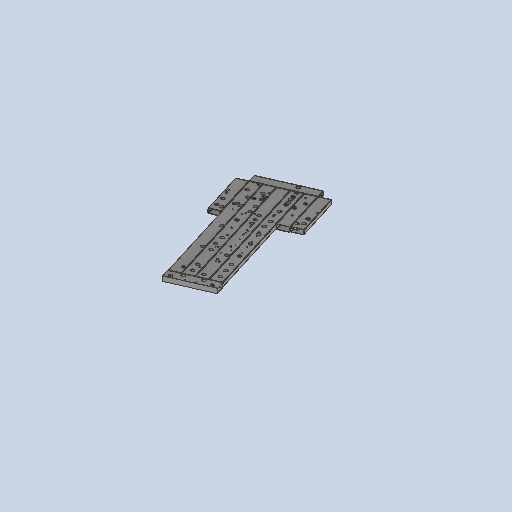
# Autodesk Inventor part: Bauteil1
Saved by Autodesk Inventor 2027.1 (Build 311270010, 270A)
## iProperties
Created: 2026-07-23
Part Number: Bauteil1
Material: Stahl, Kohlenstoff
Document SubType Name: Modeling
Designer: Leander
Density: 7.85 g/cm^3
Appearance: Halbpoliert
Author: Leander
Autodesk Inventor part; units mm, degrees
ref_plane "YZ Plane" through (0, 0, 0) normal (1, 0, 0) x (0, 1, 0)
ref_plane "XZ Plane" through (0, 0, 0) normal (0, 1, 0) x (-1, 0, 0)
sketch "Skizze1" plane through (0, 0, 0) normal (0, 0, 1) x (1, 0, 0)
  line L0 (0, 0) -> (700, 0)
  line L1 (700, 0) -> (700, 1705)
  line L2 (700, 1705) -> (0, 1705)
  line L3 (0, 1705) -> (0, 0)
  line L4 (100, 0) -> (100, 1099)
  line L5 (100, 1099) -> (0, 1099)
  line L6 (0, 1099) -> (0, 1604)
  line L7 (0, 1604) -> (100, 1604)
  line L8 (100, 1604) -> (100, 1705)
  line L9 (100, 1705) -> (600, 1705)
  line L10 (600, 1705) -> (600, 1604)
  line L11 (600, 1604) -> (700, 1604)
  line L12 (700, 1604) -> (700, 1099)
  line L13 (700, 1099) -> (600, 1099)
  line L14 (600, 1099) -> (600, 1089.4)
  line L15 (600, 1089.4) -> (500, 1089.4)
  line L16 (500, 1089.4) -> (500, 0)
  line L17 (100, 0) -> (500, 0)
  circle A0 centre (146.4, 28.6) radius 12.6
  circle A1 centre (146.4, 28.6) radius 16.5
  circle A2 centre (223.4, 69.6) radius 12.6
  circle A3 centre (223.4, 69.6) radius 16.5
  circle A4 centre (373.6, 69.6) radius 12.6
  circle A5 centre (373.6, 69.6) radius 16.5
  circle A6 centre (450.8, 28.6) radius 12.6
  circle A7 centre (450.8, 28.6) radius 16.5
  circle A8 centre (76.1, 1158) radius 12.6
  circle A9 centre (76.1, 1158) radius 16.5
  circle A10 centre (34, 1178) radius 12.6
  circle A11 centre (34, 1178) radius 16.5
  circle A12 centre (36.6, 1277.7) radius 12.6
  circle A13 centre (36.6, 1277.7) radius 16.5
  circle A14 centre (430.7, 1667) radius 12.6
  circle A15 centre (430.7, 1667) radius 16.5
  circle A16 centre (622, 1160.6) radius 12.6
  circle A17 centre (622, 1160.6) radius 16.5
  circle A18 centre (663, 1181) radius 12.6
  circle A19 centre (663, 1181) radius 16.5
  circle A20 centre (662.4, 1261) radius 12.6
  circle A21 centre (662.4, 1261) radius 16.5
  circle A22 centre (133.8, 1482.5) radius 12.6
  circle A23 centre (133.8, 1482.5) radius 16.5
  circle A24 centre (180, 1592.5) radius 12.6
  circle A25 centre (180, 1592.5) radius 16.5
  circle A26 centre (137, 1242.5) radius 12.6
  circle A27 centre (137, 1242.5) radius 16.5
  circle A28 centre (180, 1237) radius 12.6
  circle A29 centre (180, 1237) radius 16.5
  circle A30 centre (248, 174.5) radius 12.6
  circle A31 centre (248, 174.5) radius 16.5
  circle A32 centre (248, 276) radius 12.6
  circle A33 centre (248, 276) radius 16.5
  circle A34 centre (248, 525) radius 12.6
  circle A35 centre (248, 525) radius 16.5
  circle A36 centre (239, 626) radius 12.6
  circle A37 centre (239, 626) radius 16.5
  circle A38 centre (239, 1021) radius 12.6
  circle A39 centre (239, 1021) radius 16.5
  circle A40 centre (178, 1373) radius 12.6
  circle A41 centre (178, 1373) radius 16.5
  circle A42 centre (180, 892) radius 12.6
  circle A43 centre (180, 544) radius 12.6
  circle A44 centre (180, 193.5) radius 12.6
  circle A45 centre (180, 892) radius 16.5
  circle A46 centre (180, 544) radius 16.5
  circle A47 centre (180, 193.5) radius 16.5
  circle A48 centre (249, 727) radius 12.6
  circle A49 centre (251, 1476) radius 12.6
  circle A50 centre (277, 1432) radius 12.6
  circle A51 centre (251, 1476) radius 16.5
  circle A52 centre (277, 1432) radius 16.5
  circle A53 centre (249, 727) radius 16.5
  circle A54 centre (224, 1378) radius 12.6
  circle A55 centre (224, 1378) radius 16.5
  circle A56 centre (277, 1270) radius 12.6
  circle A57 centre (277, 1270) radius 16.5
  circle A58 centre (274, 1179) radius 12.6
  circle A59 centre (274, 1179) radius 16.5
  circle A60 centre (340, 151) radius 12.6
  circle A61 centre (374, 495) radius 12.6
  circle A62 centre (350, 1022) radius 12.6
  circle A63 centre (350, 1084) radius 12.6
  circle A64 centre (350, 1084) radius 16.5
  circle A65 centre (350, 1022) radius 16.5
  circle A66 centre (374, 495) radius 16.5
  circle A67 centre (340, 151) radius 16.5
  circle A68 centre (564, 1464) radius 12.6
  circle A69 centre (564, 1464) radius 16.5
  circle A70 centre (521, 1372) radius 12.6
  circle A71 centre (521, 1372) radius 16.5
  circle A72 centre (452, 174) radius 12.6
  circle A73 centre (452, 274) radius 12.6
  circle A74 centre (452, 379) radius 12.6
  circle A75 centre (452, 524) radius 12.6
  circle A76 centre (452, 729) radius 12.6
  circle A77 centre (452, 884) radius 12.6
  circle A78 centre (452, 1106) radius 12.6
  circle A79 centre (452, 1272) radius 12.6
  circle A80 centre (452, 1432) radius 12.6
  circle A81 centre (452, 1478) radius 12.6
  circle A82 centre (452, 1523) radius 12.6
  circle A83 centre (452, 1591) radius 12.55
  circle A84 centre (452, 1591) radius 16.5
  circle A85 centre (452, 1523) radius 16.5
  circle A86 centre (452, 1478) radius 16.5
  circle A87 centre (452, 1432) radius 16.5
  circle A88 centre (452, 1272) radius 16.5
  circle A89 centre (452, 1106) radius 16.5
  circle A90 centre (452, 884) radius 16.5
  circle A91 centre (452, 729) radius 16.5
  circle A92 centre (452, 524) radius 16.5
  circle A93 centre (452, 379) radius 16.5
  circle A94 centre (452, 274) radius 16.5
  circle A95 centre (452, 174) radius 16.5
  dimension "d0" = 700
  dimension "d1" = 1705
  dimension "d2" = 1099
  dimension "d3" = 505
  dimension "d4" = 500
  dimension "d5" = 505
  dimension "d6" = 100
  dimension "d7" = 9.6
  dimension "d8" = 100
  dimension "d9" = 25.2
  dimension "d_a" = 33
  dimension "d11" = 25.2
  dimension "d12" = 33
  dimension "d13" = 25.2
  dimension "d14" = 33
  dimension "d15" = 25.2
  dimension "d16" = 33
  dimension "d17" = 25.2
  dimension "d18" = 33
  dimension "d19" = 25.2
  dimension "d20" = 33
  dimension "d21" = 25.2
  dimension "d22" = 33
  dimension "d23" = 25.2
  dimension "d24" = 33
  dimension "d25" = 25.2
  dimension "d26" = 33
  dimension "d27" = 100
  dimension "d28" = 1667
  dimension "d29" = 430.7
  dimension "d30" = 1277.7
  dimension "d31" = 34
  dimension "d32" = 36.6
  dimension "d33" = 1178
  dimension "d34" = 76.1
  dimension "d35" = 1158
  dimension "d36" = 1160.6
  dimension "d37" = 622
  dimension "d40" = 223.4
  dimension "d41" = 69.6
  dimension "d42" = 373.6
  dimension "d43" = 69.6
  dimension "d44" = 28.6
  dimension "d45" = 450.8
  dimension "d46" = 25.2
  dimension "d47" = 33
  dimension "d48" = 663
  dimension "d49" = 1181
  dimension "d50" = 25.2
  dimension "d51" = 33
  dimension "d52" = 662.4
  dimension "d54" = 25.2
  dimension "d55" = 33
  dimension "d56" = 25.2
  dimension "d57" = 33
  dimension "d58" = 25.2
  dimension "d59" = 33
  dimension "d60" = 25.2
  dimension "d61" = 33
  dimension "d62" = 180
  dimension "d63" = 133.8
  dimension "d64" = 1592.5
  dimension "d65" = 1482.5
  dimension "d66" = 137
  constraints: 96 centre point, 48 coincident, 36 end point, 14 point on line, 6 perpendicular, 3 parallel, 1 collinear, 1 horizontal
  measures "d0" distance of L2.end L1.end
  measures "d1" distance of L1.end L0.end
  measures "d2" distance of L4.start L4.end
  measures "d3" distance of L5.end L6.end
  measures "d4" distance of L8.end L9.end
  measures "d5" distance of L11.end L12.end
  measures "d6" distance of L12.end L13.end
  measures "d7" distance of L13.end L14.end
  measures "d8" distance of L14.end L15.end
  measures "d9" diameter of A0
  measures "d_a" diameter of A1
  measures "d11" diameter of A2
  measures "d12" diameter of A3
  measures "d13" diameter of A4
  measures "d14" diameter of A5
  measures "d15" diameter of A6
  measures "d16" diameter of A7
  measures "d17" diameter of A8
  measures "d18" diameter of A9
  measures "d19" diameter of A10
  measures "d20" diameter of A11
  measures "d21" diameter of A12
  measures "d22" diameter of A13
  measures "d23" diameter of A14
  measures "d24" diameter of A15
  measures "d25" diameter of A16
  measures "d26" diameter of A17
  measures "d27" distance between parallel lines of L3 L4
  measures "d28" distance from line of L0 A15.centre
  measures "d29" distance from line of L3 A15.centre
  measures "d30" distance from line of L0 A12.centre
  measures "d31" distance from line of L3 A10.centre
  measures "d32" distance from line of L3 A12.centre
  measures "d33" distance from line of L17 A10.centre
  measures "d34" distance from line of L6 A8.centre
  measures "d35" distance from line of A9.centre L0
  measures "d36" distance from line of L17 A16.centre
  measures "d37" distance from line of L6 A16.centre
  measures "d40" distance from line of L3 A2.centre
  measures "d41" distance from line of L17 A2.centre
  measures "d42" distance from line of L3 A5.centre
  measures "d43" distance from line of L0 A5.centre
  measures "d44" distance from line of L0 A6.centre
  measures "d45" distance from line of L3 A6.centre
  measures "d46" diameter of A18
  measures "d47" diameter of A19
  measures "d48" distance from line of L3 A18.centre
  measures "d49" distance from line of L17 A18.centre
  measures "d50" diameter of A20
  measures "d51" diameter of A21
  measures "d52" distance from line of L3 A20.centre
  measures "d54" diameter of A22
  measures "d55" diameter of A23
  measures "d56" diameter of A24
  measures "d57" diameter of A25
  measures "d58" diameter of A26
  measures "d59" diameter of A27
  measures "d60" diameter of A28
  measures "d61" diameter of A29
  measures "d62" distance from line of L3 A24.centre
  measures "d63" distance from line of L3 A22.centre
  measures "d64" distance from line of L0 A24.centre
  measures "d65" distance from line of L0 A22.centre
  measures "d66" distance from line of L3 A26.centre
extrude "Extrusion1" add sketch "Skizze1" along normal blind 42 contours L4 L5 L3 L7 L8 L2 L10 L11 L1 L13 L14 L15 L16 L0
sketch "Skizze2" plane through (0, 0, 42) normal (0, 0, 1) x (1, 0, 0)
  circle A0 centre (25.5, 1417.5) radius 7.5
  circle A1 centre (18.5, 1390.5) radius 7.5
  circle A2 centre (28.5, 1364.5) radius 7.5
  line L0 (0, 1604) -> (0, 1099) projected
  line L1 (100, 0) -> (500, 0) projected
  circle A3 centre (155.4, 1160) radius 3.4
  circle A4 centre (158.5, 1267.5) radius 7.5
  circle A5 centre (361.9, 761.3) radius 4.25
  circle A6 centre (359.2, 852.2599) radius 4.25
  circle A7 centre (287, 1498) radius 8
  circle A8 centre (276.5, 1386) radius 16.5
  circle A9 centre (256.5, 1145.5) radius 7.5
  circle A10 centre (259, 578.4) radius 3.4
  circle A11 centre (451.7, 580.3) radius 4.25
  circle A12 centre (450.6, 671.2934) radius 4.25
  line L2 (100, 1099) -> (100, 0) projected
  circle A13 centre (237.4, 1119.4) radius 3.4
  circle A14 centre (250.5, 899) radius 7
  circle A15 centre (264, 784) radius 8
  circle A16 centre (274, 587) radius 8
  circle A17 centre (277.5, 238.5) radius 7.5
  circle A18 centre (336, 19) radius 3.4
  circle A19 centre (256.5, 16) radius 3.4
  circle A20 centre (338.5, 412.5) radius 7.5
  circle A21 centre (361, 381) radius 7.5
  circle A22 centre (339.7, 379) radius 7.5
  circle A23 centre (322, 510) radius 3.4
  circle A24 centre (371, 578) radius 3.4
  circle A25 centre (349, 631) radius 7.5
  circle A26 centre (369, 665.5) radius 3.4
  circle A27 centre (452, 764) radius 3.4
  circle A28 centre (451, 854.5) radius 3.4
  circle A29 centre (356.5, 833) radius 4.25
  circle A30 centre (367.5, 870.5) radius 3.4
  circle A31 centre (352.3, 914.25) radius 4.25
  circle A32 centre (369.5, 899) radius 5.1
  circle A33 centre (358.5, 960.5) radius 3.4
  circle A34 centre (360.5, 986) radius 5.1
  circle A35 centre (442, 914.5) radius 7.5
  circle A36 centre (439.5, 1018.5) radius 16.5
  circle A37 centre (350, 1152.5) radius 16.5
  circle A38 centre (315, 1163) radius 7.5
  circle A39 centre (440.5, 1213.5) radius 7.5
  circle A40 centre (437, 1194) radius 7.5
  circle A41 centre (452, 1386.5) radius 16.5
  circle A42 centre (547.5, 1260.5) radius 7.5
  circle A43 centre (532, 1546) radius 7.5
  circle A44 centre (684.5, 1376) radius 7.5
  point P0 (0, 0)
  dimension "d209" = 15
  dimension "d210" = 15
  dimension "d211" = 15
  dimension "d212" = 18.5
  dimension "d213" = 25.5
  dimension "d214" = 28.5
  dimension "d215" = 1417.5
  dimension "d216" = 1390.5
  dimension "d217" = 1364.5
  dimension "d218" = 6.8
  dimension "d219" = 155.4
  dimension "d220" = 1160
  dimension "d221" = 15
  dimension "d222" = 158.5
  dimension "d223" = 1267.5
  dimension "d228" = 8.5
  dimension "d229" = 361.9
  dimension "d230" = 761.3
  dimension "d231" = 8.5
  dimension "d232" = 91
  dimension "d233" = 359.2
  dimension "d238" = 16
  dimension "d239" = 33
  dimension "d240" = 15
  dimension "d241" = 6.8
  dimension "d242" = 287
  dimension "d243" = 1498
  dimension "d244" = 276.5
  dimension "d245" = 1386
  dimension "d246" = 256.5
  dimension "d247" = 1145.5
  dimension "d248" = 259
  dimension "d249" = 578.4
  dimension "d250" = 8.5
  dimension "d251" = 8.5
  dimension "d253" = 580.3
  dimension "d254" = 91
  dimension "d255" = 450.6
  dimension "d256" = 451.7
  dimension "d263" = 6.8
  dimension "d264" = 237.4
  dimension "d265" = 1119.4
  dimension "d268" = 14
  dimension "d269" = 250.5
  dimension "d270" = 899
  dimension "d271" = 16
  dimension "d272" = 264
  dimension "d273" = 784
  dimension "d274" = 16
  dimension "d275" = 274
  dimension "d276" = 587
  dimension "d277" = 15
  dimension "d278" = 277.5
  dimension "d279" = 238.5
  dimension "d280" = 6.8
  dimension "d281" = 6.8
  dimension "d282" = 256.5
  dimension "d283" = 16
  dimension "d284" = 19
  dimension "d285" = 336
  dimension "d290" = 15
  dimension "d291" = 338.5
  dimension "d292" = 412.5
  dimension "d293" = 15
  constraints: 45 centre point
  measures "d209" diameter of A0
  measures "d210" diameter of A1
  measures "d211" diameter of A2
  measures "d212" distance from line of A1.centre L0
  measures "d213" distance from line of L0 A0.centre
  measures "d214" distance from line of L0 A2.centre
  measures "d215" distance from line of L1 A0.centre
  measures "d216" distance from line of L1 A1.centre
  measures "d217" distance from line of L1 A2.centre
  measures "d218" diameter of A3
  measures "d219" distance from line of L0 A3.centre
  measures "d220" distance from line of L1 A3.centre
  measures "d221" diameter of A4
  measures "d222" distance from line of L0 A4.centre
  measures "d223" distance from line of L1 A4.centre
  measures "d228" diameter of A5
  measures "d229" distance from line of L0 A5.centre
  measures "d230" distance from line of L1 A5.centre
  measures "d231" diameter of A6
  measures "d232" distance of A6.centre A5.centre
  measures "d233" distance from line of L0 A6.centre
  measures "d238" diameter of A7
  measures "d239" diameter of A8
  measures "d240" diameter of A9
  measures "d241" diameter of A10
  measures "d242" distance from line of L0 A7.centre
  measures "d243" distance from line of L1 A7.centre
  measures "d244" distance from line of L0 A8.centre
  measures "d245" distance from line of L1 A8.centre
  measures "d246" distance from line of L0 A9.centre
  measures "d247" distance from line of L1 A9.centre
  measures "d248" distance from line of L0 A10.centre
  measures "d249" distance from line of L1 A10.centre
  measures "d250" diameter of A11
  measures "d251" diameter of A12
  measures "d253" distance from line of L1 A11.centre
  measures "d254" distance of A11.centre A12.centre
  measures "d255" distance from line of L0 A12.centre
  measures "d256" distance from line of A11.centre L0
  measures "d263" diameter of A13
  measures "d264" distance from line of L0 A13.centre
  measures "d265" distance from line of L1 A13.centre
  measures "d268" diameter of A14
  measures "d269" distance from line of L0 A14.centre
  measures "d270" distance from line of L1 A14.centre
  measures "d271" diameter of A15
  measures "d272" distance from line of L0 A15.centre
  measures "d273" distance from line of L1 A15.centre
  measures "d274" diameter of A16
  measures "d275" distance from line of L0 A16.centre
  measures "d276" distance from line of L1 A16.centre
  measures "d277" diameter of A17
  measures "d278" distance from line of L0 A17.centre
  measures "d279" distance from line of L1 A17.centre
  measures "d280" diameter of A18
  measures "d281" diameter of A19
  measures "d282" distance from line of L0 A19.centre
  measures "d283" distance from line of L1 A19.centre
  measures "d284" distance from line of L1 A18.centre
  measures "d285" distance from line of L0 A18.centre
  measures "d290" diameter of A20
  measures "d291" distance from line of L0 A20.centre
  measures "d292" distance from line of L1 A20.centre
  measures "d293" diameter of A21
extrude "Extrusion2" cut sketch "Skizze2" against normal blind 42
thread "Gewinde1" size "M8x1.25" class "6H" standard "ANSI Metric M Profile" full length
thread "Gewinde2" size "M10x1.5" class "6H" standard "ISO Metric profile" full length
thread "Gewinde3" size "M10x1.5" class "6H" standard "ISO Metric profile" full length
thread "Gewinde4" size "M8x1.25" class "6H" standard "ANSI Metric M Profile" full length
thread "Gewinde5" size "M10x1.5" class "6H" standard "ISO Metric profile" full length
thread "Gewinde6" size "M10x1.5" class "6H" standard "ISO Metric profile" full length
thread "Gewinde7" size "M8x1.25" class "6H" standard "ISO Metric profile" full length
thread "Gewinde8" size "M8x1.25" class "6H" standard "ISO Metric profile" full length
thread "Gewinde9" size "M8x1.25" class "6H" standard "ISO Metric profile" full length
thread "Gewinde10" size "M8x1.25" class "6H" standard "ISO Metric profile" full length
thread "Gewinde11" size "M8x1.25" class "6H" standard "ISO Metric profile" full length
thread "Gewinde12" size "M8x1.25" class "6H" standard "ISO Metric profile" full length
thread "Gewinde13" size "M8x1.25" class "6H" standard "ISO Metric profile" full length
thread "Gewinde14" size "M8x1.25" class "6H" standard "ISO Metric profile" full length
thread "Gewinde15" size "M10x1.5" class "6H" standard "ISO Metric profile" full length
thread "Gewinde16" size "M8x1.25" class "6H" standard "ISO Metric profile" full length
thread "Gewinde17" size "M12x1.75" class "6H" standard "ISO Metric profile" full length
thread "Gewinde18" size "M10x1.5" class "6H" standard "ISO Metric profile" full length
thread "Gewinde19" size "M8x1.25" class "6H" standard "ISO Metric profile" full length
thread "Gewinde20" size "M12x1.75" class "6H" standard "ISO Metric profile" full length
sketch "Skizze3" plane through (500, 0, 0) normal (1, 0, 0) x (0, 0, -1)
  line L0 (-3, 3) -> (-39, 3)
  line L1 (-39, 3) -> (-39, 97)
  line L2 (-39, 97) -> (-3, 97)
  line L3 (-3, 97) -> (-3, 3)
  point P0 (0, 0)
  dimension "d387" = 36
  dimension "d388" = 94
  constraints: 8 end point, 2 parallel, 1 horizontal, 1 perpendicular
  measures "d387" distance of L1.end L2.end
  measures "d388" distance of L0.end L1.end
extrude "Extrusion3" cut sketch "Skizze3" against normal blind 608.75
sketch "Skizze4" plane through (500, 0, 0) normal (1, 0, 0) x (0, 0, -1)
  line L0 (-39, 97) -> (-3, 97) projected
  line L1 (-3, 97) -> (-3, 100)
  line L2 (-3, 100) -> (0, 100)
  line L3 (0, 100) -> (-42.0133, 100)
  line L4 (0, 100) -> (-42.0133, 100)
  line L5 (-42, 1099) -> (-42, 0) projected
  line L6 (0, 100) -> (0, 95)
  line L7 (0, 1099) -> (0, 0) projected
  line L8 (0, 95) -> (0, 100)
  line L9 (0, 100) -> (0, 95)
  line L10 (0, 95) -> (-5, 95)
  circle A0 centre (-5, 95) radius 5
  line L11 (-3, 97) -> (-3, 95)
  line L12 (-5, 100) -> (-5, 95)
  point P0 (-5, 100)
  dimension "d391" = 3
  dimension "d402" = 5
  dimension "d403" = 5
  dimension "d404" = 5
  constraints: 20 end point, 4 point on line, 3 perpendicular, 2 collinear, 2 point on circle, 2 vertical, 1 centre point, 1 coincident
  measures "d391" distance of L0.end L1.end
  measures "d402" distance of L2.end L6.end
  measures "d403" distance of L6.end L2.end
  measures "d404" distance of L6.end L10.end
ref_plane "Arbeitsebene1" through (100, 100, 0) normal (0, -1, 0) x (1, 0, 0)
split body "Trennen1" result two bodies by plane through (100, 100, 0) normal (0, -1, 0) first body at (273.8037, 95.3266, 0.5)
sketch "Skizze5" plane through (100, 100, 0) normal (0, -1, 0) x (1, 0, 0)
  line L0 (3, 3) -> (97, 3)
  line L1 (97, 3) -> (97, 39)
  line L2 (97, 39) -> (3, 39)
  line L3 (3, 39) -> (3, 3)
  line L4 (103, 39) -> (197, 39)
  line L5 (197, 39) -> (197, 3)
  line L6 (197, 3) -> (103, 3)
  line L7 (103, 3) -> (103, 39)
  line L8 (203, 39) -> (297, 39)
  line L9 (297, 39) -> (297, 3)
  line L10 (297, 3) -> (203, 3)
  line L11 (203, 3) -> (203, 39)
  line L12 (303, 39) -> (397, 39)
  line L13 (397, 39) -> (397, 3)
  line L14 (397, 3) -> (303, 3)
  line L15 (303, 3) -> (303, 39)
  line L16 (100, 42) -> (95, 42)
  line L17 (95, 42) -> (95, 37)
  line L18 (95, 37) -> (100, 37)
  line L19 (100, 37) -> (100, 42)
  line L20 (100, 42) -> (105, 42)
  line L21 (105, 42) -> (105, 37)
  line L22 (105, 37) -> (100, 37)
  line L23 (100, 37) -> (100, 42)
  line L24 (400, 0) -> (0, 0) projected
  line L25 (95, 37) -> (100, 37)
  line L26 (100, 37) -> (100, 0)
  line L27 (100, 0) -> (95, 0)
  line L28 (95, 0) -> (95, 37)
  circle A0 centre (95, 5) radius 5
  circle A1 centre (95, 37) radius 5
  line L29 (0, 0) -> (0, 42) projected
  circle A2 centre (195, 37) radius 5
  line L30 (0, 42) -> (400, 42) projected
  line L31 (195, 37) -> (200, 37)
  line L32 (200, 37) -> (200, 42)
  line L33 (200, 42) -> (195, 42)
  line L34 (195, 42) -> (195, 37)
  line L35 (200, 0) -> (195, 0)
  line L36 (195, 0) -> (195, 5)
  line L37 (195, 5) -> (200, 5)
  line L38 (200, 5) -> (200, 0)
  circle A3 centre (195, 5) radius 5
  line L39 (300, 42) -> (295, 42)
  line L40 (295, 42) -> (295, 37)
  line L41 (295, 37) -> (300, 37)
  line L42 (300, 37) -> (300, 42)
  circle A4 centre (295, 37) radius 5
  line L43 (300, 0) -> (295, 0)
  line L44 (295, 0) -> (295, 5)
  line L45 (295, 5) -> (300, 5)
  line L46 (300, 5) -> (300, 0)
  circle A5 centre (295, 5) radius 5
  point P0 (-100, 0)
  point P1 (203, 21)
  point P2 (100, 5)
  dimension "d393" = 94
  dimension "d394" = 36
  dimension "d395" = 94
  dimension "d396" = 94
  dimension "d397" = 36
  dimension "d398" = 94
  dimension "d399" = 36
  dimension "d451" = 5
  dimension "d452" = 5
  dimension "d453" = 5
  dimension "d454" = 5
  dimension "d455" = 6
  dimension "d456" = 3
  dimension "d457" = 6
  dimension "d458" = 6
  dimension "d459" = 5
  dimension "d460" = 5
  dimension "d461" = 5
  dimension "d462" = 5
  dimension "d463" = 5
  constraints: 88 end point, 22 parallel, 11 horizontal, 11 perpendicular, 8 point on line, 4 coincident, 3 midpoint, 1 centre point, 1 tangent, 15 other
  measures "d393" distance of L2.end L1.end
  measures "d394" distance of L1.end L0.end
  measures "d395" distance of L5.end L6.end
  measures "d396" distance of L9.end L10.end
  measures "d397" distance of L8.end L9.end
  measures "d398" distance of L13.end L14.end
  measures "d399" distance of L12.end L13.end
  measures "d451" distance of L18.end L17.end
  measures "d452" distance of L17.end L16.end
  measures "d453" distance of L21.end L22.end
  measures "d454" distance of L20.end L21.end
  measures "d455" distance from line of point (203, 21) L5
  measures "d456" distance between parallel lines of L29 L3
  measures "d457" distance between parallel lines of L15 L9
  measures "d458" distance between parallel lines of L7 L1
  measures "d459" distance of L36.end L37.end
  measures "d460" distance of L41.end L40.end
  measures "d461" distance of L40.end L39.end
  measures "d462" distance of L44.end L45.end
  measures "d463" distance of L43.end L44.end
extrude "Extrusion4" cut sketch "Skizze5" against normal blind 1505 contours L3 L2 A1 L28 A0 L0 | A0 L28 L0 | L28 A0 L1 L0 | L28 A1 L1 A0 | A0 L26 L24 | L2 L17 L28 A1 | L28 L18 L1 A1 | L2 L1 L18 L17 | L16 L19 A1 | A3 L38 L24 | L36 L37 L5 L6 | L6 A3 L5 L37 L36 | L6 L7 L22 L21 L4 A2 L5 A3 | L7 L4 L21 L22 | A5 L46 L24 | L30 L32 A2 | L44 L45 L9 L10 | L10 A5 L9 L45 L44 | L10 L11 L8 A4 L9 A5 | A2 L4 L34 L31 L5 | L4 L5 L31 L34 | L30 L42 A4 | A4 L8 L40 L41 L9 | L8 L9 L41 L40 | L12 L13 L14 L15 picked at (94.5912, 7.6158) picked at (96.3333, 5.1942) picked at (193.4725, 3.6667) picked at (296.3333, 6.5275) picked at (193.4725, 38.3333) picked at (296.3333, 35.4725) bodies 3
extrude "Extrusion5" cut sketch "Skizze4" against normal blind 1505 contours L3 L1 A0 | A0 L1 L2 L6 bodies 2
sketch "Skizze6" plane through (500, 1089.4, 42) normal (1, 0, 0) x (0, 0, -1)
  line L0 (0, -989.4) -> (0, -994.4)
  line L1 (0, -989.4) -> (0, -1089.4) projected
  line L2 (0, -994.4) -> (5, -994.4)
  circle A0 centre (5, -994.4) radius 5
  line L3 (0, -989.4) -> (5, -989.4)
  line L4 (37, -989.4) -> (0, -989.4) projected
  point P0 (42, -1089.4)
  dimension "d407" = 5
  dimension "d408" = 5
  constraints: 6 end point, 2 point on circle, 2 point on line, 1 centre point, 1 coincident, 1 perpendicular
  measures "d407" distance of L0.start L0.end
  measures "d408" distance of L0.end L2.end
extrude "Extrusion6" cut sketch "Skizze6" against normal blind 1505 contours L3 A0 L0 bodies 2
fillet "Rundung1" radius 5 8 edges at (100, 599.5, 42) (500, 594.7, 42) (500, 594.7, 0) (100, 599.5, 0) (700, 1351.5, 42) (700, 1351.5, 0) (0, 1351.5, 42) (0, 1351.5, 0)
sketch "Skizze7" plane through (600, 1604, 0) normal (1, 0, 0) x (0, 0, -1)
  line L0 (-3, 3) -> (-39, 3)
  line L1 (-39, 3) -> (-39, 97)
  line L2 (-39, 97) -> (-3, 97)
  line L3 (-3, 97) -> (-3, 3)
  line L4 (-42, 0) -> (-37, 0) projected
  line L5 (-42, 0) -> (-37, 0)
  line L6 (-37, 0) -> (-37, 5)
  line L7 (-37, 5) -> (-42, 5)
  line L8 (-42, 5) -> (-42, 0)
  circle A0 centre (-37, 5) radius 5
  line L9 (0, -28) -> (0, 5) projected
  line L10 (0, 0) -> (-5, 0)
  line L11 (-5, 0) -> (-5, 5)
  line L12 (-5, 5) -> (0, 5)
  line L13 (0, 5) -> (0, 0)
  circle A1 centre (-5, 5) radius 5
  point P0 (0, -1604)
  dimension "d412" = 36
  dimension "d413" = 94
  dimension "d416" = 5
  dimension "d417" = 5
  dimension "d418" = 5
  dimension "d419" = 5
  constraints: 24 end point, 6 parallel, 3 horizontal, 3 perpendicular, 2 coincident, 1 point on line, 6 other
  measures "d412" distance of L1.end L2.end
  measures "d413" distance of L0.end L1.end
  measures "d416" distance of L7.end L6.end
  measures "d417" distance of L6.end L5.end
  measures "d418" distance of L11.end L12.end
  measures "d419" distance of L10.end L11.end
extrude "Extrusion7" cut sketch "Skizze7" against normal blind 1505 contours L0 L11 L12 L3 | L0 A1 L3 L12 L11 | L0 A0 L1 L2 L3 A1 | A1 L9 L10 | L0 L6 L7 L1 A0 | L0 L1 L7 L6 | L4 L8 A0 picked at (-3.6667, 6.5275) picked at (-35.4725, 3.6667) bodies 3
fillet "Rundung2" radius 5 2 edges at (350, 1705, 0) (350, 1705, 42)
sketch "Skizze8" plane through (600, 1089.4, 0) normal (0, -1, 0) x (1, 0, 0)
  line L0 (-597, 3) -> (-503, 3)
  line L1 (-503, 3) -> (-503, 39)
  line L2 (-503, 39) -> (-597, 39)
  line L3 (-597, 39) -> (-597, 3)
  line L4 (-97, 3) -> (-3, 3)
  line L5 (-3, 3) -> (-3, 39)
  line L6 (-3, 39) -> (-97, 39)
  line L7 (-97, 39) -> (-97, 3)
  line L8 (3, 3) -> (97, 3)
  line L9 (97, 3) -> (97, 39)
  line L10 (97, 39) -> (3, 39)
  line L11 (3, 39) -> (3, 3)
  arc A0 (-595, 42) -> (-600, 37) centre (-595, 37) ccw projected
  line L12 (-600, 42) -> (-595, 42)
  line L13 (-595, 42) -> (-595, 37)
  line L14 (-595, 37) -> (-600, 37)
  line L15 (-600, 37) -> (-600, 42)
  line L16 (-595, 0) -> (-495, 0) projected
  line L17 (-500, 0) -> (-505, 0)
  line L18 (-505, 0) -> (-505, 5)
  line L19 (-505, 5) -> (-500, 5)
  line L20 (-500, 5) -> (-500, 0)
  line L21 (-500, 42) -> (-505, 42)
  line L22 (-505, 42) -> (-505, 37)
  line L23 (-505, 37) -> (-500, 37)
  line L24 (-500, 37) -> (-500, 42)
  circle A1 centre (-505, 37) radius 5
  circle A2 centre (-505, 5) radius 5
  line L25 (-100, 42) -> (-95, 42)
  line L26 (-95, 42) -> (-95, 37)
  line L27 (-95, 37) -> (-100, 37)
  line L28 (-100, 37) -> (-100, 42)
  line L29 (-100, 0) -> (-95, 0)
  line L30 (-95, 0) -> (-95, 5)
  line L31 (-95, 5) -> (-100, 5)
  line L32 (-100, 5) -> (-100, 0)
  line L33 (0, 37) -> (0, 42) projected
  line L34 (0, 42) -> (-5, 42)
  line L35 (-5, 42) -> (-5, 37)
  line L36 (-5, 37) -> (0, 37)
  line L37 (0, 37) -> (0, 42)
  line L38 (0, 0) -> (-5, 0)
  line L39 (-5, 0) -> (-5, 5)
  line L40 (-5, 5) -> (0, 5)
  line L41 (0, 5) -> (0, 0)
  line L42 (0, 0) -> (5, 0)
  line L43 (5, 0) -> (5, 5)
  line L44 (5, 5) -> (0, 5)
  line L45 (0, 5) -> (0, 0)
  line L46 (0, 42) -> (5, 42)
  line L47 (5, 42) -> (5, 37)
  line L48 (5, 37) -> (0, 37)
  line L49 (0, 37) -> (0, 42)
  line L50 (100, 42) -> (95, 42)
  line L51 (95, 42) -> (95, 37)
  line L52 (95, 37) -> (100, 37)
  line L53 (100, 37) -> (100, 42)
  line L54 (100, 0) -> (95, 0)
  line L55 (95, 0) -> (95, 5)
  line L56 (95, 5) -> (100, 5)
  line L57 (100, 5) -> (100, 0)
  circle A3 centre (-95, 37) radius 5
  circle A4 centre (-95, 5) radius 5
  circle A5 centre (-5, 5) radius 5
  circle A6 centre (-5, 37) radius 5
  circle A7 centre (5, 37) radius 5
  circle A8 centre (5, 5) radius 5
  point P0 (-600, 0)
  point P1 (-509.5826, 3)
  point P2 (-503, 9.5826)
  point P3 (-503, 32.4174)
  point P4 (-509.5826, 39)
  point P5 (-595, 39)
  point P6 (-597, 37)
  point P7 (9.5826, 3)
  point P8 (95, 3)
  point P9 (97, 5)
  point P10 (97, 37)
  point P11 (95, 39)
  point P12 (9.5826, 39)
  point P13 (3, 32.4174)
  point P14 (3, 9.5826)
  point P15 (-3, 32.4174)
  point P16 (-9.5826, 39)
  point P17 (-90.4174, 39)
  point P18 (-97, 32.4174)
  point P19 (-97, 9.5826)
  point P20 (-90.4174, 3)
  point P21 (-9.5826, 3)
  point P22 (-3, 9.5826)
  dimension "d421" = 94
  dimension "d422" = 36
  dimension "d423" = 94
  dimension "d424" = 36
  dimension "d425" = 94
  dimension "d426" = 36
  dimension "d427" = 5
  dimension "d428" = 5
  dimension "d429" = 5
  dimension "d430" = 5
  dimension "d431" = 5
  dimension "d432" = 5
  dimension "d433" = 5
  dimension "d434" = 5
  dimension "d435" = 5
  dimension "d436" = 5
  dimension "d437" = 5
  dimension "d438" = 5
  dimension "d439" = 5
  dimension "d440" = 5
  dimension "d441" = 5
  dimension "d442" = 5
  dimension "d443" = 5
  dimension "d444" = 5
  dimension "d445" = 5
  dimension "d446" = 5
  constraints: 112 end point, 28 parallel, 14 horizontal, 14 perpendicular, 8 coincident, 8 point on line, 24 other
  measures "d421" distance of L2.end L1.end
  measures "d422" distance of L1.end L0.end
  measures "d423" distance of L6.end L5.end
  measures "d424" distance of L5.end L4.end
  measures "d425" distance of L10.end L9.end
  measures "d426" distance of L9.end L8.end
  measures "d427" distance of L18.end L19.end
  measures "d428" distance of L17.end L18.end
  measures "d429" distance of L23.end L22.end
  measures "d430" distance of L22.end L21.end
  measures "d431" distance of L26.end L27.end
  measures "d432" distance of L25.end L26.end
  measures "d433" distance of L31.end L30.end
  measures "d434" distance of L30.end L29.end
  measures "d435" distance of L36.end L35.end
  measures "d436" distance of L35.end L34.end
  measures "d437" distance of L39.end L40.end
  measures "d438" distance of L38.end L39.end
  measures "d439" distance of L44.end L43.end
  measures "d440" distance of L43.end L42.end
  measures "d441" distance of L47.end L48.end
  measures "d442" distance of L46.end L47.end
  measures "d443" distance of L52.end L51.end
  measures "d444" distance of L51.end L50.end
  measures "d445" distance of L55.end L56.end
  measures "d446" distance of L54.end L55.end
extrude "Extrusion8" cut sketch "Skizze8" against normal blind 514.6 contours L3 L14 L13 L2 A1 L1 A2 L0 | A2 L1 L19 L18 L0 | L3 L2 L13 L14 | L18 L19 L1 L0 | A2 L20 L16 | A1 L2 L22 L23 L1 | L23 L22 L2 L1 | A1 L21 L24 | L7 L31 L30 L4 | L30 L31 L7 A4 L4 | A4 L7 A3 L6 A6 L5 A5 L4 | L29 L32 A4 | A5 L5 L40 L39 L4 | L7 L27 L26 L6 A3 | L39 L40 L5 L4 | A5 L41 L38 | L7 L6 L26 L27 | L28 L25 A3 | A6 L6 L35 L36 L5 | A8 L42 L41 | L36 L35 L6 L5 | A6 L34 L33 | L33 L46 A7 | L44 L43 L8 L11 | L11 A8 L8 L43 L44 | L11 A7 L10 L51 L52 L9 L56 L55 L8 A8 | L48 L47 L10 A7 L11 | L11 L10 L47 L48 | L55 L56 L9 L8 | L10 L9 L52 L51 picked at (-503.6667, 6.5275) picked at (-503.6667, 35.4725) picked at (-93.4725, 3.6667) picked at (-6.5275, 3.6667) picked at (-93.4725, 38.3333) picked at (-3.6667, 35.4725) picked at (6.5275, 3.6667) picked at (6.5275, 38.3333) bodies 3
fillet "Rundung3" radius 5 3 edges at (100, 1351.5, 42) (100, 1351.5, 0) (500, 1346.7, 0)
fillet "Rundung4" radius 5 1 edges at (500, 1346.7, 42)
fillet "Rundung5" radius 5 6 edges at (200, 852, 42) (300, 852, 42) (400, 852, 42) (400, 852, 0) (300, 852, 0) (200, 852, 0)
equation "\"a15\" = 15"
equation "\"M8\" = 6.8"
equation "\"M10\" = 8.5"
equation "\"a14\" = 14"
equation "\"a33\" = 33"
equation "\"M12\" = 10.2"
equation "\"M5\" = 4.2"
equation "\"M4\" = 3.3"
